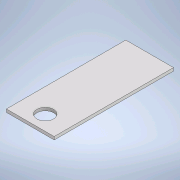
# Autodesk Inventor part: Rotorschutz_BT2
Saved by Autodesk Inventor 2020.1 (Build 241239000, 239)
## iProperties
Created: 2020-08-20
Part Number: Rotorschutz_BT2
Material: Generisch
Document SubType Name: Modeling
Designer: s5chfeis
Density: 1 g/cm^3
Appearance: Vorgabe
Author: s5chfeis
Autodesk Inventor part; units mm, degrees
ref_plane "YZ Plane" through (0, 0, 0) normal (1, 0, 0) x (0, 1, 0)
ref_plane "XZ Plane" through (0, 0, 0) normal (0, 1, 0) x (-1, 0, 0)
ref_plane "XY Plane" through (0, 0, 0) normal (0, 0, 1) x (1, 0, 0)
sketch "Skizze1" plane through (0, 0, 0) normal (0, 1, 0) x (-1, 0, 0)
  line L0 (0, 0) -> (-80, 0)
  line L1 (-80, 0) -> (-80, 200)
  line L2 (-80, 200) -> (0, 200)
  line L3 (0, 200) -> (0, 0)
  dimension "d0" = 80
  dimension "d1" = 200
  constraints: 8 end point, 2 parallel, 1 horizontal, 1 perpendicular
  measures "d0" distance of L1.end L2.end
  measures "d1" distance of L0.end L1.end
extrude "Extrusion1" add sketch "Skizze1" along normal blind 5
sketch "Skizze2" plane through (0, 5, 0) normal (0, 1, 0) x (1, 0, 0)
  line L0 (0, -200) -> (80, -200) construction
  line L1 (40, -200) -> (40, 0) construction
  line L2 (40, -200) -> (240, -200) construction
  line L3 (80, -200) -> (80, -175) construction
  line L4 (80, -200) -> (80, 0) construction
  line L5 (80, -200) -> (105, -200) construction
  line L6 (80, -175) -> (0, -175) construction
  line L7 (0, 0) -> (0, -200) construction
  circle A0 centre (40, -175) radius 14
  dimension "d4" = 200
  dimension "d5" = 90
  dimension "d6" = 25
  dimension "d7" = 90
  dimension "d8" = 80
  dimension "d9" = 90
  dimension "d10" = 28
  constraints: 10 end point, 3 perpendicular, 2 horizontal, 2 midpoint, 1 centre point, 1 collinear, 1 vertical
  measures "d4" distance of L1.start L1.end
  measures "d5" angle of L2 L1
  measures "d6" distance of L0.end L3.end
  measures "d7" angle of L5 L3
  measures "d8" distance of L3.end L6.end
  measures "d9" angle of L6 L3
  measures "d10" diameter of A0
extrude "Extrusion2" cut sketch "Skizze2" against normal blind 10
